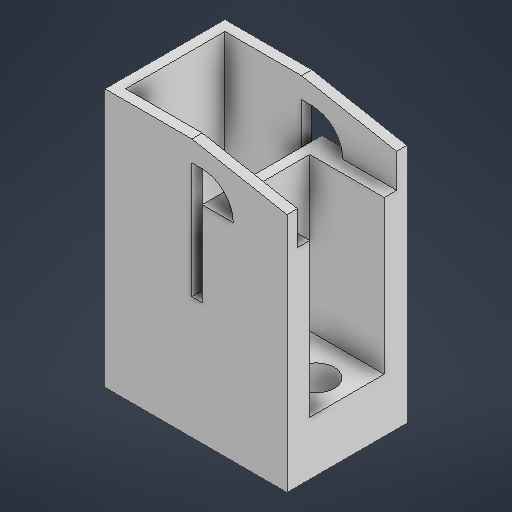
# Autodesk Inventor part: Motor Mount
Saved by Autodesk Inventor 2026.2 (Build 302298000, 298)
## iProperties
Created: 2026-11-09
Part Number: Motor Mount
Material: Generic
Document SubType Name: Modeling
Designer: Carro
Density: 1 g/cm^3
Appearance: Default
Author: Carro
Autodesk Inventor part; units mm, degrees
ref_plane "YZ Plane" through (0, 0, 0) normal (1, 0, 0) x (0, 1, 0)
ref_plane "XZ Plane" through (0, 0, 0) normal (0, 1, 0) x (-1, 0, 0)
ref_plane "XY Plane" through (0, 0, 0) normal (0, 0, 1) x (1, 0, 0)
sketch "Sketch1" plane through (0, 0, 0) normal (0, 1, 0) x (-1, 0, 0)
  line L0 (-11.43, 6.096) -> (11.43, 6.096)
  line L1 (11.43, 6.096) -> (11.43, -6.096)
  line L2 (11.43, -6.096) -> (-11.43, -6.096)
  line L3 (-11.43, -6.096) -> (-11.43, 6.096)
  line L4 (-11.43, 6.096) -> (11.43, -6.096) construction
  line L5 (11.43, 6.096) -> (-11.43, -6.096) construction
  point P0 (0, 0)
  dimension "d0" = 22.86
  dimension "d1" = 12.192
  constraints: 12 end point, 2 midpoint, 2 parallel, 1 horizontal, 1 perpendicular
  measures "d0" distance of L0.start L0.end
  measures "d1" distance of L0.end L1.end
extrude "Base" add sketch "Sketch1" along normal blind 2.54
sketch "Sketch2" plane through (0, 2.54, 0) normal (0, 1, 0) x (1, 0, 0)
  line L0 (-11.43, -6.096) -> (11.43, -6.096) projected
  line L1 (11.43, 6.096) -> (-11.43, 6.096) projected
  line L2 (-4.7244, -6.096) -> (-4.7244, 6.096) construction
  line L3 (-4.7244, 0) -> (0, 0) construction
  line L4 (-4.7244, -6.096) -> (-8.2169, -6.096)
  line L5 (-8.2169, -6.096) -> (-8.2169, -2.6035)
  line L6 (-8.2169, -2.6035) -> (-4.7244, -2.6035)
  line L7 (-4.7244, -2.6035) -> (-4.7244, -6.096)
  line L8 (-4.7244, 6.096) -> (-8.2169, 6.096)
  line L9 (-8.2169, 6.096) -> (-8.2169, 2.6035)
  line L10 (-8.2169, 2.6035) -> (-4.7244, 2.6035)
  line L11 (-4.7244, 2.6035) -> (-4.7244, 6.096)
  line L12 (-6.4707, 2.6035) -> (-6.4706, -2.6035) construction
  line L13 (-6.4707, 0) -> (-11.43, 0) construction
  line L14 (-11.43, 6.096) -> (-11.43, -6.096) construction
  point P0 (-8.2169, 6.096)
  point P1 (-8.2169, -6.096)
  point P2 (-8.2169, 6.096)
  point P3 (-8.2169, -6.096)
  dimension "d4" = 3.4925
  dimension "d5" = 3.4925
  dimension "d25" = 4.9593
  constraints: 24 end point, 5 midpoint, 4 horizontal, 4 parallel, 3 perpendicular, 2 equal length, 2 point on line
  measures "d4" distance of L5.end L6.end
  measures "d5" distance of L4.end L5.end
  measures "d25" distance of L13.start L13.end
sketch "Sketch3" plane through (0, 2.54, 0) normal (0, 1, 0) x (1, 0, 0)
  line L0 (0, 0) -> (-1.397, 0) construction
  line L1 (-0.762, -5.08) -> (-0.762, 5.08)
  line L2 (-0.762, 5.08) -> (-2.032, 5.08)
  line L3 (-2.032, 5.08) -> (-2.032, -5.08)
  line L4 (-2.032, -5.08) -> (-0.762, -5.08)
  line L5 (-0.762, -5.08) -> (-2.032, 5.08) construction
  line L6 (-0.762, 5.08) -> (-2.032, -5.08) construction
  line L7 (-0.762, 0) -> (-11.43, 0) construction
  line L8 (-11.43, 6.096) -> (-11.43, -6.096) projected
  dimension "d6" = 1.27
  dimension "d7" = 10.16
  dimension "d27" = 10.668
  constraints: 16 end point, 4 midpoint, 2 horizontal, 2 parallel, 2 perpendicular
  measures "d6" distance of L1.end L2.end
  measures "d7" distance of L2.end L3.end
  measures "d27" distance of L7.start L7.end
extrude "Motor Wire Holes" cut sketch "Sketch2" against normal through all
extrude "Sensor Wire Hole" cut sketch "Sketch3" against normal through all
sketch "Sketch4" plane through (0, 0, 0) normal (0, -1, 0) x (1, 0, 0)
  line L0 (11.43, 6.096) -> (11.43, -6.096) projected
  line L1 (11.43, -6.096) -> (-11.43, -6.096) projected
  line L2 (11.43, 6.096) -> (-11.43, 6.096)
  line L3 (-11.43, 6.096) -> (-11.43, -6.096)
  line L4 (-11.43, -6.096) -> (11.43, -6.096)
  line L5 (11.43, -6.096) -> (11.43, 6.096)
  line L6 (12.7, -7.366) -> (-12.7, -7.366)
  line L7 (-12.7, -7.366) -> (-12.7, 7.366)
  line L8 (-12.7, 7.366) -> (12.7, 7.366)
  line L9 (12.7, 7.366) -> (12.7, -7.366)
  line L10 (12.7, -7.366) -> (11.43, -7.366)
  line L11 (11.43, -7.366) -> (11.43, 7.366)
  line L12 (11.43, 7.366) -> (12.7, 7.366)
  line L13 (12.7, 7.366) -> (12.7, -7.366)
  line L14 (11.43, 6.096) -> (11.43, -6.096) projected
  point P0 (0, 0)
  point P1 (-8.2169, -6.096)
  point P2 (11.43, -6.096)
  point P3 (11.43, 6.096)
  point P4 (11.43, -7.366)
  dimension "d12" = 1.27
  constraints: 24 end point, 6 parallel, 3 perpendicular, 2 horizontal, 1 collinear, 1 point on line, 3 other
  measures "d12" distance between parallel lines of L4 L6
extrude "Walls" add sketch "Sketch4" against normal blind 29.21 contours L2 L3 L1 L11 L6 L7 L8
sketch "Sketch6" plane through (0, 2.54, 0) normal (0, 1, 0) x (1, 0, 0)
  line L0 (0, 0) -> (-0.127, 0) construction
  line L1 (0.508, 6.096) -> (0.508, -6.096)
  line L2 (0.508, -6.096) -> (-0.762, -6.096)
  line L3 (-0.762, -6.096) -> (-0.762, 6.096)
  line L4 (-0.762, 6.096) -> (0.508, 6.096)
  line L5 (0.508, 6.096) -> (-0.762, -6.096) construction
  line L6 (0.508, -6.096) -> (-0.762, 6.096) construction
  line L7 (-0.762, 5.08) -> (-0.762, -5.08) projected
  line L8 (-0.762, 0) -> (0.508, 0)
  line L9 (-11.43, 6.096) -> (11.43, 6.096) projected
  line L10 (11.43, -6.096) -> (-11.43, -6.096) projected
  line L11 (-0.762, 0) -> (-11.43, 0) construction
  line L12 (-11.43, 6.096) -> (-11.43, -6.096) projected
  point P0 (19.05, 9.525)
  point P1 (11.43, 6.096)
  dimension "d20" = 1.27
  dimension "d21" = 1.27
  dimension "d26" = 10.668
  constraints: 18 end point, 5 midpoint, 2 horizontal, 2 parallel, 2 perpendicular, 1 collinear, 1 vertical, 1 other
  measures "d20" distance of L1.end L2.end
  measures "d21" distance of L8.end L8.start
  measures "d26" distance of L11.start L11.end
extrude "Divider" add sketch "Sketch6" along normal blind 22.86 contours L1 L8 L3 L4 | L1 L2 L3 L8
sketch "Sketch7" plane through (0, 2.54, 0) normal (0, 1, 0) x (1, 0, 0)
  circle A0 centre (5.842, 0) radius 2.25
  line L0 (5.842, 0) -> (0.508, 0) construction
  line L1 (0.508, -6.096) -> (0.508, 6.096) construction
  circle A1 centre (5.842, 0) radius 2 construction
  point P0 (0, 0)
  point P1 (3.592, 0)
  point P2 (3.842, 0)
  dimension "d28" = 4.5
  dimension "d68" = 4
  dimension "d29" = 5.334
  constraints: 2 end point, 2 horizontal alignment, 2 midpoint, 2 point on line, 1 coincident, 1 horizontal, 4 other
  measures "d29" distance of L0.end L0.start
extrude "Heat Sink 4M" cut sketch "Sketch7" against normal blind 25.4
sketch "Sketch8" plane through (0, 2.54, 0) normal (0, 1, 0) x (1, 0, 0)
  line L0 (0.508, -6.096) -> (0.508, 6.096) projected
  line L1 (0.508, -6.096) -> (11.43, -6.096)
  line L2 (11.43, -6.096) -> (11.43, 6.096)
  line L3 (11.43, 6.096) -> (0.508, 6.096)
  line L4 (0.508, 6.096) -> (0.508, -6.096)
  line L5 (0.508, -4.572) -> (11.43, -4.572)
  line L6 (0.508, 4.572) -> (11.43, 4.572)
  line L7 (5.969, -4.572) -> (5.969, -6.096) construction
  line L8 (5.969, 4.572) -> (5.969, 6.096) construction
  point P0 (0, 0)
  dimension "d32" = 9.144
  constraints: 16 end point, 4 midpoint, 4 point on line, 3 perpendicular, 2 parallel, 1 collinear, 1 horizontal
  measures "d32" distance between parallel lines of L6 L5
extrude "Linear Act Enclosure" add sketch "Sketch8" along normal up to surface (22.86 mm away) contours L0 L5 L2 L1 | L0 L3 L2 L6
sketch "Sketch9" plane through (0, 29.21, 0) normal (0, 1, 0) x (1, 0, 0)
  line L0 (-12.7, -7.366) -> (11.43, -7.366) projected
  line L1 (11.43, 7.366) -> (-12.7, 7.366) projected
  line L2 (-0.762, -7.366) -> (-2.032, -7.366)
  line L3 (-2.032, -7.366) -> (-2.032, 7.366)
  line L4 (-2.032, 7.366) -> (-0.762, 7.366)
  line L5 (-0.762, 7.366) -> (-0.762, -7.366)
  line L6 (-2.032, -5.08) -> (-2.032, 5.08) projected
  line L7 (-0.762, -6.096) -> (-0.762, 6.096) projected
  point P0 (0, 0)
  constraints: 8 end point, 2 collinear, 2 parallel, 2 point on line, 1 horizontal, 1 perpendicular
extrude "Pressure Sensor Side Holes" cut sketch "Sketch9" against normal blind 14.224
thicken "Thicken1" operation add thickness 2.54 both sides no extend neighbours no toward (0, 1, 0) faces at (-12.2767, 29.21, 2.032)
sketch "Sketch12" plane through (-12.7, 0, 7.366) normal (0, 0, 1) x (1, 0, 0)
  line L0 (11.938, 29.21) -> (24.13, 29.21) projected
  line L1 (10.668, 14.986) -> (10.668, 31.75) projected
  line L2 (10.668, 31.75) -> (24.13, 29.21)
  line L3 (11.938, 29.21) -> (10.668, 29.21)
  point P0 (12.7, 0)
  constraints: 4 end point, 1 horizontal, 1 point on line
extrude "Extrusion11" add sketch "Sketch12" against normal up to surface (1.27 mm away)
mirror "Mirror2" about plane through (0, 0, 0) normal (0, 0, 1) of "Extrusion11"
sketch "Sketch17" plane through (-8.2169, 0, -6.096) normal (0, 0, 1) x (1, 0, 0)
  line L0 (7.4549, 25.4) -> (19.6469, 25.4) projected
  line L1 (7.4549, 29.21) -> (7.4549, 25.4) projected
  arc A0 (11.2649, 25.4) -> (7.4549, 29.21) centre (7.4549, 25.4) ccw
  point P0 (8.2169, 0)
  constraints: 2 point on circle, 1 centre point, 1 coincident, 1 point on line
extrude "Extrusion16" cut sketch "Sketch17" against normal through all
mirror "Mirror3" about plane through (0, 0, 0) normal (0, 0, 1) of "Extrusion16"
sketch "Sketch19" plane through (11.43, 0, 7.366) normal (1, 0, 0) x (0, 0, -1)
  line L0 (14.732, 0) -> (14.732, 31.75) projected
  line L1 (0, 0) -> (14.732, 0)
  line L2 (14.732, 0) -> (14.732, 31.75)
  line L3 (14.732, 31.75) -> (0, 31.75)
  line L4 (0, 31.75) -> (0, 0)
  point P0 (7.366, 0)
  constraints: 8 end point, 2 parallel, 1 horizontal, 1 perpendicular
extrude "Extrusion18" cut sketch "Sketch19" against normal blind 1.778
thicken "Thicken3" operation add thickness 4.064 both sides no extend neighbours no toward (0, 1, 0) faces at (1.536, 2.54, 0)
body "Solid1"
